Autodesk Fusion 360 part; units mm, degrees
(part 3 of 4)
equation "fix_xbl = door_xbr + ( door_zb - fix_zb ) * ( door_xbr - door_xtr ) / ( door_zt - door_zb ) + glass_gap * sqrt(( door_xbr - door_xtr ) * ( door_xbr - door_xtr ) + ( door_zt - door_zb ) * ( door_zt - door_zb )) / ( door_zt - door_zb )" comment "SKELETON P04 CALCULATION: F-014: fixed glass bottom-left, on the line glass_gap from the door's slanted edge (was v1's 1468)"
equation "fix_xtl = door_xbr + ( door_zb - fix_zt ) * ( door_xbr - door_xtr ) / ( door_zt - door_zb ) + glass_gap * sqrt(( door_xbr - door_xtr ) * ( door_xbr - door_xtr ) + ( door_zt - door_zb ) * ( door_zt - door_zb )) / ( door_zt - door_zb )" comment "SKELETON P04 CALCULATION: F-014: fixed glass top-left, on the same line (was v1's 1184)"
equation "floor_top = mat_t + floor_t" comment "SKELETON P04 CALCULATION: D-72: the floor top, Z 12 (mat 3 + ply 9); the threshold stands thresh_h above the room floor"
equation "wall_z0 = glide_h + band_h" comment "SKELETON P04 CALCULATION: base band top: glides + band"
equation "panel_z0 = wall_z0 + seam_gap" comment "SKELETON P04 CALCULATION: walls stand one seam_gap above the band top (joints register 2.8, IF-01)"
equation "wall_h = pod_h - wall_z0" comment "SKELETON P04 CALCULATION: 2290 = layout study v2_model wall_h"
equation "side_h = ( wall_h - 2 * seam_gap ) / 2" comment "SKELETON P04 CALCULATION: D-23: 2 sheets per side wall; the gap on the band and the horizontal seam (joints register 2.8)"
equation "side_l = wall_depth - seam_gap" comment "SKELETON P04 CALCULATION: side panel length along Y: the seam_gap at the decor's back plate (joints register 2.8, IF-07)"
equation "back_oh = pod_h - outer_t - seam_gap - panel_z0" comment "SKELETON P04 CALCULATION: PM ruling 2026-10-31 (pass D, F-004): the back outer frames run up to the ceiling frame (pod_h - outer_t), less the seam_gap under it, closing the slot at the back top edge"
equation "back_ph = ( back_oh - seam_gap ) / 2" comment "SKELETON P04 CALCULATION: D-23: 4 sheets on the back, two equal rows with one seam_gap between them (joints register 2.8); the lower back linings match the lower row, as on the side walls"
equation "half_pw = ( pod_w - 2 * outer_t - 3 * seam_gap ) / 2" comment "SKELETON P04 CALCULATION: SKIN width of each back and ceiling panel: two skins and three seam_gap seams between the side frames (F-001, joints register 2.8)"
equation "close_gap = 5.5 mm" comment "SKELETON P04 DECIDED: PM ruling 2026-10-31 (joints register, F-011/F-012): frame gap at the closing seams B1-B2, B3-B4 and C1-C2, which have no hard stop (slotted holes, thicker gasket)"
equation "half_fw = ( pod_w - 2 * outer_t - 2 * seam_gap - close_gap ) / 2" comment "SKELETON P04 CALCULATION: FRAME width of each back and ceiling panel: the skins overhang their frames by half_pw - half_fw at the closing seam (PM ruling 2026-10-31)"
equation "inner_w = pod_w - 2 * stack_t" comment "SKELETON P04 CALCULATION: inside width between the side linings"
equation "bolt_edge_inset = 220 mm" comment "SKELETON P04 DECIDED: PM ruling 2026-10-31: on every bolted edge the end bolts sit this far in from each panel end (the FRAME end, where the bolts go), the rest evenly spaced"
equation "spigot_inset = 100 mm" comment "SKELETON P04 DECIDED: PM ruling 2026-10-31: locating spigots this far in from each panel end (round hole at one end, slot at the other)"
equation "base_bolt_edge = bolt_edge_inset" comment "SKELETON P04 DECIDED: J-BASE-01 wall to band: the edge rule (kept by this name for parts already linked)"
equation "n_base_bolt = 4" comment "SKELETON P04 DECIDED: PM ruling 2026-10-31, J-BASE-01: bolts per panel along the band, evenly spaced"
equation "base_spigot_inset = spigot_inset" comment "SKELETON P04 DECIDED: J-BASE-01: the spigot rule (kept by this name for parts already linked)"
equation "base_side_y0 = pod_d / 2 - wall_depth + seam_gap" comment "SKELETON P04 CALCULATION: J-BASE-01: side bolt lines start at the side panel's front end (first bolt base_bolt_edge further on)"
equation "side_base_pitch = ( side_l - 2 * base_bolt_edge ) / ( n_base_bolt - 1 )" comment "SKELETON P04 CALCULATION: J-BASE-01 bolt pitch along a side panel"
equation "base_back_x0 = pod_w / 2 - outer_t - seam_gap" comment "SKELETON P04 CALCULATION: J-BASE-01: back bolt lines start at each back FRAME's outer end, X -/+ this (first bolt base_bolt_edge further in)"
equation "back_base_pitch = ( half_fw - 2 * base_bolt_edge ) / ( n_base_bolt - 1 )" comment "SKELETON P04 DECIDED: PM ruling 2026-10-31 (Reviewer 5 P2 on #58): J-BASE-01 pitch along a back panel, measured on the FRAME (half_fw), where the bolts go; 'panel end' means the frame end"
equation "ceil_bolt_z = pod_h - outer_t + frame_t / 2" comment "SKELETON P04 DECIDED: PM ruling 2026-10-31, J-CEIL-01 wall to ceiling: the bolt line on the ceiling frame's centre (Z 2374)"
equation "n_ceil_side_bolt = 4" comment "SKELETON P04 DECIDED: PM ruling 2026-10-31, J-CEIL-01: bolts along each side wall top"
equation "n_ceil_back_bolt = 4" comment "SKELETON P04 DECIDED: PM ruling 2026-10-31, J-CEIL-01: bolts along each back panel top, like the base (pitch about 253, every edge 350 or less; joints register: 82 bolts in all)"
equation "ceil_side_y0 = pod_d / 2 - wall_depth" comment "SKELETON P04 DECIDED: PM ruling 2026-10-31 (joints register): J-CEIL-01 side bolt lines start at Y -645, measured along the ceiling (first bolt bolt_edge_inset further on)"
equation "ceil_side_pitch = ( wall_depth - 2 * bolt_edge_inset ) / ( n_ceil_side_bolt - 1 )" comment "SKELETON P04 DECIDED: PM ruling 2026-10-31 (joints register): J-CEIL-01 pitch along a side wall top, over the ceiling's length (was over the side panel's)"
equation "ceil_back_x0 = pod_w / 2 - outer_t - seam_gap" comment "SKELETON P04 DECIDED: PM ruling 2026-10-31 (joints register): J-CEIL-01 back bolt lines start at each back frame's outer end, X -/+ this"
equation "ceil_back_pitch = ( half_fw - 2 * bolt_edge_inset ) / ( n_ceil_back_bolt - 1 )" comment "SKELETON P04 DECIDED: PM ruling 2026-10-31 (joints register): J-CEIL-01 pitch along a back panel top, on the frame (half_fw)"
equation "sk_ref = 5000 mm" comment "ASSUMPTION: sketch reference point offset: every sketch corner is dimensioned from a point at -sk_ref on both plane axes, so no dimension changes side when a corner crosses a pod centre line in an edit"
equation "fg_vis_zb = wall_z0" comment "CALCULATION: visible bottom of the fixed pane = the base band top (DL and DR stop there too, PM ruling 2026-10-31)"
equation "fg_vis_zt = dt_zb" comment "CALCULATION: visible top of the fixed pane = DT's underside"
equation "fg_gap = glass_gap" comment "CALCULATION: = the skeleton's glass_gap: the pane's free edge runs parallel to the door's latch edge, 4 mm off (PM ruling 2026-10-31; the skeleton's fix_xbl and fix_xtl follow the same rule since its update #58)"
equation "gu_prof_w = 15 mm" comment "SOURCE: Bohle BO5201571 aluminium U-profile 15 x 15 x 1.5 (hardware selection C5)"
equation "gu_prof_d = 15 mm" comment "SOURCE: as gu_prof_w"
equation "gu_prof_t = 1.5 mm" comment "SOURCE: as gu_prof_w"
equation "gu_w = gu_prof_w - 2 * gu_prof_t" comment "CALCULATION: inner width of the U-profile = the U-seal's outer width"
equation "gu_base = 2 mm" comment "ASSUMPTION: U-seal base under the glass edge; HOLD for Bohle's BO5201735 section drawing"
equation "gu_in_d = gu_prof_d - gu_prof_t" comment "CALCULATION: inner depth of the U-profile"
equation "fg_bite = gu_in_d - gu_base" comment "CALCULATION: glass cover in the hidden channels, 11.5 (PM ruling 2026-10-31); HOLD for the glass supplier's minimum"
equation "fg_r_len = sqrt(( fix_xbr - fix_xk ) * ( fix_xbr - fix_xk ) + ( fix_zk - fix_zb ) * ( fix_zk - fix_zb ))" comment "CALCULATION: length of the skeleton's right edge (bottom-right corner to the knee)"
equation "fg_rnx = ( fix_zk - fix_zb ) / fg_r_len" comment "CALCULATION: right edge outward normal, X"
equation "fg_rnz = ( fix_xk - fix_xbr ) / fg_r_len" comment "CALCULATION: right edge outward normal, Z"
equation "fg_rc = fg_rnx * ( pod_w / 2 - fix_xbr ) + fg_rnz * fix_zb" comment "CALCULATION: right edge line constant"
equation "fg_d_len = sqrt(( pod_w - fix_xtr - fix_xk ) * ( pod_w - fix_xtr - fix_xk ) + ( dt_zb - fix_zk ) * ( dt_zb - fix_zk ))" comment "CALCULATION: length of DR's diagonal inner edge (knee to DT's underside at X -pod_w/2 + fix_xtr)"
equation "fg_dnx = ( dt_zb - fix_zk ) / fg_d_len" comment "CALCULATION: diagonal outward normal, X"
equation "fg_dnz = ( pod_w - fix_xtr - fix_xk ) / fg_d_len" comment "CALCULATION: diagonal outward normal, Z"
equation "fg_dc = fg_dnx * ( pod_w / 2 - fix_xk ) + fg_dnz * fix_zk" comment "CALCULATION: diagonal line constant"
equation "fg_det = fg_rnx * fg_dnz - fg_rnz * fg_dnx" comment "CALCULATION: for the knee corner"
equation "fg_l_len = sqrt(( door_xbr - door_xtr ) * ( door_xbr - door_xtr ) + ( door_zt - door_zb ) * ( door_zt - door_zb ))" comment "CALCULATION: length of the door's latch edge"
equation "fg_lnx = ( door_zt - door_zb ) / fg_l_len" comment "CALCULATION: door latch edge normal toward the pane, X"
equation "fg_lnz = ( door_xbr - door_xtr ) / fg_l_len" comment "CALCULATION: door latch edge normal toward the pane, Z"
equation "fg_lc = fg_lnx * ( -pod_w / 2 + door_xbr ) + fg_lnz * door_zb" comment "CALCULATION: door latch edge line constant"
equation "jf_x = pod_w / 2 - skin_t - bond_t - frame_t / 2" comment "CALCULATION: joints register J-FRONT-01: the side panel's front member centre line, X -/+1224 (skin, bond line and half the 40 frame in from the outside, skeleton named values)"
equation "jf_hole = 9.53 mm" comment "SOURCE: rivnut 838003 (Sherex CAH2-610-4.2, zinc-plated steel, D-131) hole 9.53 +0.10/0, as the aluminium part's (joints register H-03; unverified for the steel part, HOLD-04)"
equation "jf_z1 = panel_z0 + bolt_edge_inset" comment "CALCULATION: lower panel, bottom bolt (220 rule)"
equation "jf_z2 = panel_z0 + side_h / 2" comment "CALCULATION: lower panel, middle bolt"
equation "jf_z3 = panel_z0 + side_h - bolt_edge_inset" comment "CALCULATION: lower panel, top bolt"
equation "jf_z4 = panel_z0 + side_h + seam_gap + bolt_edge_inset" comment "CALCULATION: upper panel, bottom bolt"
equation "jf_z5 = panel_z0 + side_h + seam_gap + side_h / 2" comment "CALCULATION: upper panel, middle bolt"
equation "jf_z6 = panel_z0 + 2 * side_h + seam_gap - bolt_edge_inset" comment "CALCULATION: upper panel, top bolt"
equation "dr_skin_t = 3 mm" comment "SOURCE: ACP 3 mm, EV3038 Dark Yellow (D-12; hardware selection A1)"
equation "dr_fo = dr_skin_t + bond_t" comment "CALCULATION: a frame tube's face from the skin's outer face: the 3 mm ACP and the 3 mm bond line (skeleton bond_t; the bond spec's joint, at least 12 wide x 3 thick, D-137), so every tube that bonds to the skin stands 3 mm off it (PM ruling 2026-11-01)"
equation "dr_back_t = 1.5 mm" comment "CONFIRMED: joints register J-FRONT-01: the back plate is aluminium 1.0 to 2.7 thick at each bolt, for the rivnuts (HOLD-10); 1.5, not 2, so DR stays under 20 kg (D-03; PM ruling 2026-11-01)"
equation "fr_hole_rn = 10 mm" comment "SOURCE: D-163 (PM ruling 2026-11-01): the rivnut 838003 is Sherex CAL2-610-4.2, the knurled round body, in a round drilled hole 10.00 +0.10 (was 9.53 for the half-hex CAH2, whose body needs a hex hole); every rivnut hole in DR, the J-FRONT-01 strip's and the hook studs' too (DL and DT take it in their next rebuild)"
equation "dr_strip_x0 = jf_x - 2 * fr_hole_rn - 0.5 mm" comment "CALCULATION: the fixed back strip's inner edge, 2 hole diameters plus 0.5 from the J-FRONT-01 rivnut holes (mechanical check C09); the rest of the back comes off for the air unit (D-87)"
equation "dr_acc_t = 3 mm" comment "CALCULATION: access panel 3 mm aluminium: it carries the air column's 10 kg on two hook studs 222 mm from its screwed edge (PM ruling 2026-11-01); 2 mm would see about 110 MPa if the column pulls 50 N, 3 mm about 50 MPa"
equation "dr_rn_head = 0.76 mm" comment "SOURCE: rivnut 838003 head 0.76 +/-0.08 (joints register H-03: Sherex CAH2-610-4.2, zinc-plated steel, D-131)"
equation "dr_stop_w = 1.6 mm" comment "SOURCE: an 838004 washer (ISO 7093 6.4 x 18, 1.6 thick) on each rivnut head: the panel's stop (Joints, D-130)"
equation "dr_pnl_gap = dr_rn_head + dr_stop_w" comment "CALCULATION: the inner face panel stands 2.36 off the frame on its stops; the 4.0 seal 848013 is squeezed to it (D-130)"
equation "dr_seal_w = 8 mm" comment "SOURCE: 848013 access panel seal, about 8 wide (joints register H-34; D-130)"
equation "dr_seal_t = 4 mm" comment "SOURCE: 848013 access panel seal, 4.0 thick very soft foam (joints register H-34)"
equation "dr_pitch = 400 mm" comment "SOURCE: the panel's screws about 400 apart (Joints' seal and stop pair, D-130)"
equation "dr_drop = 40 mm" comment "CALCULATION: service: with the column off, the panel drops 40 to clear the soffit's underside (its top edge is 35 over it), then comes out (PM ruling 2026-11-01)"
equation "dr_pull = 100 mm" comment "CALCULATION: service: how far out the model shows the dropped panel coming"
equation "dr_acc_face_y = -pod_d / 2 + decor_d - dr_back_t + dr_pnl_gap + dr_acc_t" comment "CALCULATION: named value for AIR (PM rulings 2026-11-01, D-130): the room-side face of DR's inner face panel, where AIR's air column and soffit start; Y -641.14, the 3 mm panel 2.36 off the frame on its stops"
equation "dr_piece_x0 = 1150 mm" comment "CONFIRMED: with the band behind the soffit dropped, the back plate keeps a short piece from here to the side above the access panel: the soffit stops at X 1161 (AIR), 11 short of it (PM ruling 2026-11-01)"
equation "dr_band_dz = 35 mm" comment "CALCULATION: the back plate's top band starts this far above DT's underside: the removable panels' top edges land 35 on the frame's band tube, so the access panel's top bolts sit 2 hole diameters from its edge and the rivnuts 2 from the tube's edge (C09); the access panel keeps 45 over the opening into the column"
equation "dr_stud_x = 971 mm" comment "SOURCE: PM ruling 2026-11-01 (CEILING): the air column's two hook studs at X 971"
equation "dr_stud_z1 = 1700 mm" comment "SOURCE: PM ruling 2026-11-01 (CEILING): lower hook stud Z 1700"
equation "dr_stud_z2 = 1850 mm" comment "SOURCE: PM ruling 2026-11-01 (CEILING): upper hook stud Z 1850"
equation "felt_t = 9 mm" comment "SOURCE: the factory's 9 mm PET felt (D-31; hardware selection A3)"
equation "dr_col_x0 = 949 mm" comment "SOURCE: air report 7f (AIR #91): the air column's left face, X 949 (column X 949 to 1161)"
equation "dr_col_x1 = 1161 mm" comment "SOURCE: air report 7f (AIR #91; calc.py D60 col): the air column's right edge, X 1161, AIR's named value (D-130)"
equation "dr_f_len = sqrt(dr_xc * dr_xc + ( pod_d / 2 - dr_yc ) * ( pod_d / 2 - dr_yc ))" comment "CALCULATION: length of DR's corner facet in plan"
equation "dr_fnx = ( pod_d / 2 - dr_yc ) / dr_f_len" comment "CALCULATION: corner facet outward normal, X"
equation "dr_fny = -dr_xc / dr_f_len" comment "CALCULATION: corner facet outward normal, Y"
equation "dr_fc = dr_fnx * ( pod_w / 2 - dr_xc ) + dr_fny * ( -pod_d / 2 )" comment "CALCULATION: corner facet line constant"
equation "ri_x0 = 959 mm" comment "SOURCE: the D-60 air table's riser X 956 to 1095, moved 3 mm right with DR's 3 mm bond line so it keeps its 5.9 to B07 (AIR's change, CEILING Engineer 2026-11-01)"
equation "ri_w = 139 mm" comment "SOURCE: D-60 air table: riser 139 wide"
equation "ri_y0 = -803 mm" comment "SOURCE: D-60 air table: riser Y -803 to -648"
equation "ri_d = 155 mm" comment "SOURCE: D-60 air table: riser 155 deep"
equation "ri_zt = 1445 mm" comment "SOURCE: D-60 air table: riser up to Z 1445"
equation "ri_gap = 140 mm" comment "ASSUMPTION: the riser's open foot stands 140 mm over DR's open base, so the air rises straight into it and the riser clears the back frame's inner-edge member B07 by 5.9 mm (the glass line runs to X 950 there; the riser moved 3 mm right with the 3 mm bond line); was 60 before the frame"
equation "slot_clear = 1 mm" comment "ASSUMPTION: fitting clearance each side of the glass channel in DR's skin slot"
equation "ri_t = 1 mm" comment "SOURCE: D-60 air table: 1 mm galvanised steel"
equation "fb_w = 300 mm" comment "SOURCE: D-60 air table: fan box 300 x 155 x 300"
equation "fb_d = 155 mm" comment "SOURCE: D-60 air table"
equation "fb_z0 = 1650 mm" comment "SOURCE: D-60 air table: fan box Z 1650 to 1950"
equation "fb_x0 = 680 mm" comment "SOURCE: fan box left side, X 680 to 980 (PM ruling 2026-11-01, from the AIR Transitions Engineer's check: with the 3 mm bond line the box's lower-left back corner came within 1.0 of the back ring's diagonal B06; 7 mm right it keeps 6.3 to B06, 8.1 to the front ring's diagonal F05 and 17.3 to the fixed glass channel); AIR's model has the same X (sb_x0)"
equation "fb_h = 300 mm" comment "SOURCE: D-60 air table"
equation "fb_t = 2 mm" comment "SOURCE: D-60 air table: 2 mm aluminium"
equation "op_x0 = 961 mm" comment "SOURCE: air report 7f: the opening into the column from X 961"
equation "op_w = 185 mm" comment "SOURCE: the opening X 961 to 1146 (PM ruling 2026-11-01, from the AIR Transitions Engineer: the upper duct's gasket face and every metal edge keep 6 from the bolt-line tube and the band; it ran to the column's edge, 200 x 215)"
equation "op_z0 = 1895 mm" comment "SOURCE: D-60 air table: opening Z 1895 to 2102 (PM ruling 2026-11-01)"
equation "op_h = 207 mm" comment "SOURCE: Z 1895 to 2102 (PM ruling 2026-11-01, the AIR Transitions Engineer; was 215)"
equation "fr_w = 20 mm" comment "CALCULATION: frame tube 20 x 20 x 1.5, 6063-T6 (D-79): bending stiffness E*I = 4.5e8 N.mm2, about v1's 16 x 16 x 1 steel box (4.7e8), at 0.30 kg/m against 0.47"
equation "fr_t = 1.5 mm" comment "CALCULATION: frame tube wall 1.5 where AIR's supply fan box (8.8 kg) stands: the shelf tubes F08 and C03"
equation "fr_t_rn = 1.2 mm" comment "CONFIRMED: wall of the ledge tube B05, which carries DT's two spigot rivnuts: 1.2, as D-85 kept the wall panels' perimeter members for their rivnuts (PM ruling 2026-11-01); the tubes under the inner face panel take fr_t_pnl"
equation "fr_t_pnl = 1.5 mm" comment "SOURCE: wall of the tubes under the inner face panel that take its rivnuts: 1.5 or more, as 1.0 is marginal for an M6 rivnut (Joints, D-130)"
equation "fr_t_sk = 1.0 mm" comment "CONFIRMED: wall of the tubes that only hold the skin and the plates: 1.0, as D-85's inner studs (PM ruling 2026-11-01, DR under 20 kg, D-03); E*I 3.2e8 N.mm2, two thirds of v1's 16 x 16 x 1 steel box, with the ACP bonded on"
equation "fr_wb = 80 mm" comment "CALCULATION: bolt-line tube 80 x 20 x 1.5 behind the fixed strip: the J-FRONT-01 rivnut tails and bolt tips go into it through 14 mm holes (HOLD-10: the plate with the frame behind), and the access panel lands 37 on its other side, wide enough for its bolts and rivnuts at 2 diameters from every edge (C09); 3 clear of the duct spaces"
equation "fr_wbot = 40 mm" comment "ASSUMPTION: back ring's bottom tube 40 x 20 x 1.5: the access panel's lower bolts"
equation "fr_wband = 60 mm" comment "ASSUMPTION: band tube 60 x 20 x 1.5 at DT's underside: the access panel's top bolts and the top band's rivets land on it"
equation "fr_h1 = 724 mm" comment "SOURCE: v1 decor frame drawing (front frame): first cross tube 724 above the bottom"
equation "fb_gap = 5 mm" comment "ASSUMPTION: the fan box's front, clear behind the front ring's cross tube F09"
equation "fb_y0 = -pod_d / 2 + dr_fo + fr_w + fb_gap" comment "CALCULATION: fan box front, Y -819: the D-60 table's -847 moved back behind the cross tube F09 (PM ruling 2026-11-01, D-131), and 3 more with the bond line so F09 keeps its 5 mm (PM ruling 2026-11-01); AIR's model follows (sb_yf)"
equation "fr_hole_jf = 14 mm" comment "CALCULATION: hole in the bolt-line tube's back wall round each J-FRONT-01 rivnut: body 9.50 max and its bulge (SHX), and the bolt tip, go into the tube"
equation "dr_sp_x1 = 1050 mm" comment "CONFIRMED: J-FRONT-02: DR's round spigot hole (PM ruling 2026-11-01)"
equation "dr_sp_x2 = 1147 mm" comment "CONFIRMED: J-FRONT-02: DR's spigot slot, along X (PM ruling 2026-11-01)"
equation "sp_hole = 8.5 mm" comment "SOURCE: R-J13: spigot hole 8.5 round at one end, 8.5 x 14 slot at the other"
equation "sp_slot = 14 mm" comment "SOURCE: R-J13: the slot 14 long along the edge"
equation "dt_sp_x1 = -pod_w / 2 + dt_xr - 179 mm" comment "CONFIRMED: J-FRONT-03: DT's round-hole spigot on DR's ledge, X 270, 36 in from the ledge tube's left end"
equation "dt_sp_dx = 140 mm" comment "CONFIRMED: J-FRONT-03: DT's slot spigot 140 from the first (PM ruling 2026-11-01)"
equation "dt_sp_y = -pod_d / 2 + decor_d - 12.88 mm" comment "CALCULATION: J-FRONT-03: the spigots' Y, -657.88, the middle of where DR's ledge tube and DT's bottom back tube overlap"
equation "ab_hole = 7 mm" comment "SOURCE: the pod's M6 clearance hole, 7.0 (D-64, D-75; the mechanical check's hole rule M6-CLEARANCE-7) for the inner face panel's screws 838001"
equation "ab_x = pod_w / 2 - dr_fo - fr_wb + 2 * fr_hole_rn + 2 mm" comment "CALCULATION: the panel's screw line on the bolt-line tube: the rivnut 2 diameters plus 2 from the tube's inner edge (C09)"
equation "ab_zt = fg_vis_zt + 2 * fr_hole_rn + 1 mm" comment "CALCULATION: the panel's screw line on the band tube: its rivnuts 2 diameters plus 1 above the tube's lower edge (C09)"
equation "dr_sc_clear = 40 mm" comment "CALCULATION: the panel's end screws 40 from the corners of its screw line, clear of the frame's welded corners (D-130)"
equation "dr_hd_d = 12 mm" comment "SOURCE: a plain M6 washer 838011 under each panel screw's head, ISO 7089 6.4 x 12 x 1.6, 200 HV zinc-plated steel (PM rulings 2026-11-01: the socket heads stay, one 5 mm key on site; the 18 mm washer made every felt hole break out; joints register H-44)"
equation "dr_felt_web = 3 mm" comment "CALCULATION: felt left between each felt hole and the felt's edge (PM ruling 2026-11-01)"
equation "dr_felt_hole = dr_hd_d + 2 mm" comment "CALCULATION: closed felt holes over the panel's screw heads: the washer and 1 mm round it, each plugged with felt cut from the same sheet (no bare socket heads on the room side); the screws stand 10 from the felt's edges, so dr_felt_web stays (PM rulings 2026-11-01)"
equation "dr_cl = sqrt(( pod_d / 2 - ch_yb ) * ( pod_d / 2 - ch_yb ) + ( pod_h - ch_zlo ) * ( pod_h - ch_zlo ))" comment "CALCULATION: length of the top chamfer in the side view"
equation "dr_cny = -( pod_h - ch_zlo ) / dr_cl" comment "CALCULATION: top chamfer outward normal, Y"
equation "dr_cnz = ( pod_d / 2 - ch_yb ) / dr_cl" comment "CALCULATION: top chamfer outward normal, Z"
equation "dr_cc = dr_cny * ( -pod_d / 2 ) + dr_cnz * ch_zlo" comment "CALCULATION: top chamfer line constant"
equation "dr_jl = sqrt(( dt_xr - fix_xtr ) * ( dt_xr - fix_xtr ) + ( pod_d / 2 - ch_yb ) * ( pod_d / 2 - ch_yb ))" comment "CALCULATION: length of the DR-DT joint line in plan (v1's line to X 449)"
equation "dr_jnx = ( pod_d / 2 - ch_yb ) / dr_jl" comment "CALCULATION: DR-DT joint normal into DR, X"
equation "dr_jny = -( dt_xr - fix_xtr ) / dr_jl" comment "CALCULATION: DR-DT joint normal into DR, Y"
equation "dr_jc = dr_jnx * ( -pod_w / 2 + fix_xtr ) + dr_jny * ( -pod_d / 2 )" comment "CALCULATION: DR-DT joint line constant"
equation "dr_pl0x = ( ( fg_rc + dr_fo + fr_w / 2 - ( ( fg_vis_zb + fr_wbot / 2 ) * fg_rnz ) ) / fg_rnx )" comment "CALCULATION: the inner face panel's screw line, corner 0, X"
equation "dr_pl0z = ( ( fg_rnx * ( fg_vis_zb + fr_wbot / 2 ) ) / fg_rnx )" comment "CALCULATION: the inner face panel's screw line, corner 0, Z"
equation "dr_pl1x = ( -( -ab_x ) )" comment "CALCULATION: the inner face panel's screw line, corner 1, X"
equation "dr_pl1z = ( -( -( fg_vis_zb + fr_wbot / 2 ) ) )" comment "CALCULATION: the inner face panel's screw line, corner 1, Z"
equation "dr_pl2x = ( -( -ab_x ) )" comment "CALCULATION: the inner face panel's screw line, corner 2, X"
equation "dr_pl2z = ( -( -ab_zt ) )" comment "CALCULATION: the inner face panel's screw line, corner 2, Z"
equation "dr_pl3x = ( -( -( -pod_w / 2 + dt_xr + fr_w / 2 ) ) )" comment "CALCULATION: the inner face panel's screw line, corner 3, X"
equation "dr_pl3z = ( -( -ab_zt ) )" comment "CALCULATION: the inner face panel's screw line, corner 3, Z"
equation "dr_pl4x = ( -( -( -pod_w / 2 + dt_xr + fr_w / 2 ) ) )" comment "CALCULATION: the inner face panel's screw line, corner 4, X"
equation "dr_pl4z = ( -( -( fg_vis_zt - fr_w / 2 ) ) )" comment "CALCULATION: the inner face panel's screw line, corner 4, Z"
equation "dr_pl5x = ( ( ( -( fg_vis_zt - fr_w / 2 ) ) * fg_dnz - ( -( fg_dc + dr_fo + fr_w / 2 ) ) ) / ( -( -fg_dnx ) ) )" comment "CALCULATION: the inner face panel's screw line, corner 5, X"
equation "dr_pl5z = ( ( -( fg_dnx * ( -( fg_vis_zt - fr_w / 2 ) ) ) ) / ( -( -fg_dnx ) ) )" comment "CALCULATION: the inner face panel's screw line, corner 5, Z"
equation "dr_pl6x = ( ( ( fg_dc + dr_fo + fr_w / 2 ) * fg_rnz - ( ( fg_rc + dr_fo + fr_w / 2 ) * fg_dnz ) ) / ( fg_dnx * fg_rnz - ( fg_rnx * fg_dnz ) ) )" comment "CALCULATION: the inner face panel's screw line, corner 6, X"
equation "dr_pl6z = ( ( fg_dnx * ( fg_rc + dr_fo + fr_w / 2 ) - ( fg_rnx * ( fg_dc + dr_fo + fr_w / 2 ) ) ) / ( fg_dnx * fg_rnz - ( fg_rnx * fg_dnz ) ) )" comment "CALCULATION: the inner face panel's screw line, corner 6, Z"
equation "dr_pe0 = sqrt(( dr_pl1x - dr_pl0x ) * ( dr_pl1x - dr_pl0x ) + ( dr_pl1z - dr_pl0z ) * ( dr_pl1z - dr_pl0z ))" comment "CALCULATION: the inner face panel's screw line along tube B01, its length"
equation "dr_pe1 = sqrt(( dr_pl2x - dr_pl1x ) * ( dr_pl2x - dr_pl1x ) + ( dr_pl2z - dr_pl1z ) * ( dr_pl2z - dr_pl1z ))" comment "CALCULATION: the inner face panel's screw line along tube B02, its length"
equation "dr_pe2 = sqrt(( dr_pl3x - dr_pl2x ) * ( dr_pl3x - dr_pl2x ) + ( dr_pl3z - dr_pl2z ) * ( dr_pl3z - dr_pl2z ))" comment "CALCULATION: the inner face panel's screw line along tube B08, its length"
equation "dr_pe3 = sqrt(( dr_pl4x - dr_pl3x ) * ( dr_pl4x - dr_pl3x ) + ( dr_pl4z - dr_pl3z ) * ( dr_pl4z - dr_pl3z ))" comment "CALCULATION: the inner face panel's screw line along tube B04, its length"
equation "dr_pe4 = sqrt(( dr_pl5x - dr_pl4x ) * ( dr_pl5x - dr_pl4x ) + ( dr_pl5z - dr_pl4z ) * ( dr_pl5z - dr_pl4z ))" comment "CALCULATION: the inner face panel's screw line along tube B05, its length"
equation "dr_pe5 = sqrt(( dr_pl6x - dr_pl5x ) * ( dr_pl6x - dr_pl5x ) + ( dr_pl6z - dr_pl5z ) * ( dr_pl6z - dr_pl5z ))" comment "CALCULATION: the inner face panel's screw line along tube B06, its length"
equation "dr_pe6 = sqrt(( dr_pl0x - dr_pl6x ) * ( dr_pl0x - dr_pl6x ) + ( dr_pl0z - dr_pl6z ) * ( dr_pl0z - dr_pl6z ))" comment "CALCULATION: the inner face panel's screw line along tube B07, its length"
equation "dr_sc_b08 = ab_x - ( pod_w / 2 - dr_fo - fr_wb ) + 2 * fr_hole_rn + 0.5 mm" comment "CALCULATION: the band tube B08's screw by the bolt-line tube from the screw line's corner: two rivnut-hole diameters and 0.5 from B08's square end at the bolt-line tube (C09's rule)"
equation "dr_sc_col = ( dr_pl0x - ( dr_col_x0 - dr_felt_hole / 2 - dr_felt_web ) ) * dr_pe6 / ( dr_pl0x - dr_pl6x )" comment "CALCULATION: the glass-edge tube B07's lowest screw from the screw line's bottom corner: its felt hole keeps dr_felt_web of felt at the air column's edge (X dr_col_x0) and its washer stands clear of the column's left face (PM ruling 2026-11-01)"
equation "d8636 = sk_ref"
equation "d8637 = sk_ref"
equation "d8638 = ( ( ( fg_rc + 0 mm - fg_rnz * ( ( fg_vis_zb - 0 mm ) ) ) / fg_rnx ) ) + sk_ref"
equation "d8639 = ( pod_w / 2 ) + sk_ref"
equation "d8640 = ( -pod_w / 2 + fix_xtr ) + sk_ref"
equation "d8641 = ( ( ( ( fg_rc + 0 mm ) * fg_dnz - ( fg_dc + 0 mm ) * fg_rnz ) / fg_det ) ) + sk_ref"
equation "d8642 = ( ( fg_vis_zb - 0 mm ) ) + sk_ref"
equation "d8643 = ( pod_h ) + sk_ref"
equation "d8644 = ( ( fg_vis_zt + 0 mm ) ) + sk_ref"
equation "d8645 = ( ( ( fg_rnx * ( fg_dc + 0 mm ) - fg_dnx * ( fg_rc + 0 mm ) ) / fg_det ) ) + sk_ref"
equation "d8646 = ( -pod_d / 2 ) * ( 1 )"
equation "d8647 = ( -pod_d / 2 + decor_d ) - ( -pod_d / 2 )"
equation "d8649 = sk_ref"
equation "d8650 = sk_ref"
equation "d8651 = ( pod_w / 2 - dr_xc ) + sk_ref"
equation "d8652 = ( pod_w / 2 ) + sk_ref"
equation "d8653 = ( -dr_yc ) + sk_ref"
equation "d8654 = ( -pod_d / 2 ) + sk_ref"
equation "d8655 = ( 0 mm ) * ( 1 )"
equation "d8656 = ( pod_h ) - ( 0 mm )"
equation "d8658 = sk_ref"
equation "d8659 = sk_ref"
equation "d8660 = ( -pod_w / 2 + dt_xr ) + sk_ref"
equation "d8661 = ( -pod_w / 2 + fix_xtr ) + sk_ref"
equation "d8662 = ( -pod_d / 2 ) + sk_ref"
equation "d8663 = ( -ch_yb ) + sk_ref"
equation "d8664 = ( -pod_d / 2 + decor_d ) + sk_ref"
equation "d8665 = ( dt_zb ) * ( 1 )"
equation "d8666 = ( pod_h ) - ( dt_zb )"
equation "d8668 = sk_ref"
equation "d8669 = sk_ref"
equation "d8670 = ( ch_zlo ) + sk_ref"
equation "d8671 = ( pod_h ) + sk_ref"
equation "d8672 = ( -ch_yb ) + sk_ref"
equation "d8673 = ( -pod_d / 2 ) + sk_ref"
equation "d8674 = ( -pod_w / 2 ) * ( 1 )"
equation "d8675 = ( pod_w / 2 ) - ( -pod_w / 2 )"
equation "d8677 = dr_skin_t"
equation "d8678 = sk_ref"
equation "d8679 = sk_ref"
equation "d8680 = ( ( ( fg_rc + 0 mm - fg_rnz * ( fg_vis_zb ) ) / fg_rnx ) ) + sk_ref"
equation "d8681 = ( ( ( fg_rc + gu_prof_d - fg_rnz * ( fg_vis_zb ) ) / fg_rnx ) ) + sk_ref"
equation "d8682 = ( ( ( ( fg_rc + gu_prof_d ) * fg_dnz - ( fg_dc + gu_prof_d ) * fg_rnz ) / fg_det ) ) + sk_ref"
equation "d8683 = ( ( ( fg_dc + gu_prof_d - fg_dnz * ( fg_vis_zt ) ) / fg_dnx ) ) + sk_ref"
equation "d8684 = ( ( ( fg_dc + 0 mm - fg_dnz * ( fg_vis_zt ) ) / fg_dnx ) ) + sk_ref"
equation "d8685 = ( ( ( ( fg_rc + 0 mm ) * fg_dnz - ( fg_dc + 0 mm ) * fg_rnz ) / fg_det ) ) + sk_ref"
equation "d8686 = ( fg_vis_zb ) + sk_ref"
equation "d8687 = ( ( ( fg_rnx * ( fg_dc + gu_prof_d ) - fg_dnx * ( fg_rc + gu_prof_d ) ) / fg_det ) ) + sk_ref"
equation "d8688 = ( fg_vis_zt ) + sk_ref"
equation "d8689 = ( ( ( fg_rnx * ( fg_dc + 0 mm ) - fg_dnx * ( fg_rc + 0 mm ) ) / fg_det ) ) + sk_ref"
equation "d8690 = ( -glass_y - gu_prof_w / 2 - slot_clear ) * ( 1 )"
equation "d8691 = ( -glass_y + gu_prof_w / 2 + slot_clear ) - ( -glass_y - gu_prof_w / 2 - slot_clear )"
equation "d8693 = sk_ref"
equation "d8694 = sk_ref"
equation "d8695 = ( ( ( dr_fc - dr_skin_t - dr_fny * ( -pod_d / 2 + dr_skin_t ) ) / dr_fnx ) ) + sk_ref"
equation "d8696 = ( ( pod_w / 2 - dr_skin_t ) ) + sk_ref"
equation "d8697 = ( ( ( fg_rc + dr_skin_t - fg_rnz * ( fg_vis_zb + dr_skin_t ) ) / fg_rnx ) ) + sk_ref"
equation "d8698 = ( ( -pod_d / 2 + dr_skin_t ) ) + sk_ref"
equation "d8699 = ( ( ( dr_fc - dr_skin_t - dr_fnx * ( pod_w / 2 - dr_skin_t ) ) / dr_fny ) ) + sk_ref"
equation "d8700 = ( -pod_d / 2 + decor_d - dr_back_t ) + sk_ref"
equation "d8701 = ( fg_vis_zb - 1 mm ) * ( 1 )"
equation "d8702 = ( fg_vis_zb + dr_skin_t + 1 mm ) - ( fg_vis_zb - 1 mm )"
equation "d8704 = sk_ref"
equation "d8705 = sk_ref"
equation "d8706 = ( pod_w / 2 - dr_skin_t ) + sk_ref"
equation "d8707 = ( -pod_w / 2 + dt_xr ) + sk_ref"
equation "d8708 = ( dr_strip_x0 ) + sk_ref"
equation "d8709 = ( fg_vis_zb + dr_skin_t ) + sk_ref"
equation "d8710 = ( pod_h - dr_skin_t ) + sk_ref"
equation "d8711 = ( fg_vis_zt + dr_band_dz ) + sk_ref"
equation "d8712 = ( -pod_d / 2 + decor_d - dr_back_t ) * ( 1 )"
equation "d8713 = ( -pod_d / 2 + decor_d ) - ( -pod_d / 2 + decor_d - dr_back_t )"
equation "d8715 = sk_ref"
equation "d8716 = sk_ref"
equation "d8717 = ( jf_x ) + sk_ref"
equation "d8718 = ( jf_z1 ) + sk_ref"
equation "d8719 = fr_hole_rn"
equation "d8720 = ( jf_x ) + sk_ref"
equation "d8721 = ( jf_z2 ) + sk_ref"
equation "d8722 = fr_hole_rn"
equation "d8723 = ( jf_x ) + sk_ref"
equation "d8724 = ( jf_z3 ) + sk_ref"
equation "d8725 = fr_hole_rn"
equation "d8726 = ( jf_x ) + sk_ref"
equation "d8727 = ( jf_z4 ) + sk_ref"
equation "d8728 = fr_hole_rn"
equation "d8729 = ( jf_x ) + sk_ref"
equation "d8730 = ( jf_z5 ) + sk_ref"
equation "d8731 = fr_hole_rn"
equation "d8732 = ( jf_x ) + sk_ref"
equation "d8733 = ( jf_z6 ) + sk_ref"
equation "d8734 = fr_hole_rn"
equation "d8735 = ( -pod_d / 2 + decor_d - dr_back_t - 1 mm ) * ( 1 )"
equation "d8736 = ( -pod_d / 2 + decor_d + 1 mm ) - ( -pod_d / 2 + decor_d - dr_back_t - 1 mm )"
equation "d8738 = sk_ref"
equation "d8739 = sk_ref"
equation "d8740 = ( ( ( fg_rc + dr_skin_t - fg_rnz * ( fg_vis_zb + dr_skin_t ) ) / fg_rnx ) ) + sk_ref"
equation "d8741 = ( dr_strip_x0 ) + sk_ref"
equation "d8742 = ( -pod_w / 2 + dt_xr ) + sk_ref"
equation "d8743 = ( ( ( fg_dc + dr_skin_t - fg_dnz * ( fg_vis_zt ) ) / fg_dnx ) ) + sk_ref"
equation "d8744 = ( ( ( ( fg_rc + dr_skin_t ) * fg_dnz - ( fg_dc + dr_skin_t ) * fg_rnz ) / fg_det ) ) + sk_ref"
equation "d8745 = ( fg_vis_zb + dr_skin_t ) + sk_ref"
equation "d8746 = ( fg_vis_zt + dr_band_dz ) + sk_ref"
equation "d8747 = ( fg_vis_zt ) + sk_ref"
equation "d8748 = ( ( ( fg_rnx * ( fg_dc + dr_skin_t ) - fg_dnx * ( fg_rc + dr_skin_t ) ) / fg_det ) ) + sk_ref"
equation "d8749 = ( dr_acc_face_y - dr_acc_t ) * ( 1 )"
equation "d8750 = ( dr_acc_face_y ) - ( dr_acc_face_y - dr_acc_t )"
equation "d8752 = sk_ref"
equation "d8753 = sk_ref"
equation "d8754 = ( op_x0 + op_w ) + sk_ref"
equation "d8755 = ( op_x0 ) + sk_ref"
equation "d8756 = ( op_z0 ) + sk_ref"
equation "d8757 = ( op_z0 + op_h ) + sk_ref"
equation "d8758 = ( dr_acc_face_y - dr_acc_t - 1 mm ) * ( 1 )"
equation "d8759 = ( dr_acc_face_y + 1 mm ) - ( dr_acc_face_y - dr_acc_t - 1 mm )"
equation "d8761 = sk_ref"
equation "d8762 = sk_ref"
equation "d8763 = ( dr_pl0x + ( dr_pl1x - dr_pl0x ) * ( ( dr_sc_clear + 0 * ( dr_pe0 - dr_sc_clear - dr_sc_clear ) / 1 ) / dr_pe0 ) ) + sk_ref"
equation "d8764 = ( dr_pl0z + ( dr_pl1z - dr_pl0z ) * ( ( dr_sc_clear + 0 * ( dr_pe0 - dr_sc_clear - dr_sc_clear ) / 1 ) / dr_pe0 ) ) + sk_ref"
equation "d8765 = ab_hole"
equation "d8766 = ( dr_pl0x + ( dr_pl1x - dr_pl0x ) * ( ( dr_sc_clear + 1 * ( dr_pe0 - dr_sc_clear - dr_sc_clear ) / 1 ) / dr_pe0 ) ) + sk_ref"
equation "d8767 = ( dr_pl0z + ( dr_pl1z - dr_pl0z ) * ( ( dr_sc_clear + 1 * ( dr_pe0 - dr_sc_clear - dr_sc_clear ) / 1 ) / dr_pe0 ) ) + sk_ref"
equation "d8768 = ab_hole"
equation "d8769 = ( dr_pl1x + ( dr_pl2x - dr_pl1x ) * ( ( dr_sc_clear + 0 * ( dr_pe1 - dr_sc_clear - dr_sc_clear ) / 5 ) / dr_pe1 ) ) + sk_ref"
equation "d8770 = ( dr_pl1z + ( dr_pl2z - dr_pl1z ) * ( ( dr_sc_clear + 0 * ( dr_pe1 - dr_sc_clear - dr_sc_clear ) / 5 ) / dr_pe1 ) ) + sk_ref"
equation "d8771 = ab_hole"
equation "d8772 = ( dr_pl1x + ( dr_pl2x - dr_pl1x ) * ( ( dr_sc_clear + 1 * ( dr_pe1 - dr_sc_clear - dr_sc_clear ) / 5 ) / dr_pe1 ) ) + sk_ref"
equation "d8773 = ( dr_pl1z + ( dr_pl2z - dr_pl1z ) * ( ( dr_sc_clear + 1 * ( dr_pe1 - dr_sc_clear - dr_sc_clear ) / 5 ) / dr_pe1 ) ) + sk_ref"
equation "d8774 = ab_hole"
equation "d8775 = ( dr_pl1x + ( dr_pl2x - dr_pl1x ) * ( ( dr_sc_clear + 2 * ( dr_pe1 - dr_sc_clear - dr_sc_clear ) / 5 ) / dr_pe1 ) ) + sk_ref"
equation "d8776 = ( dr_pl1z + ( dr_pl2z - dr_pl1z ) * ( ( dr_sc_clear + 2 * ( dr_pe1 - dr_sc_clear - dr_sc_clear ) / 5 ) / dr_pe1 ) ) + sk_ref"
equation "d8777 = ab_hole"
equation "d8778 = ( dr_pl1x + ( dr_pl2x - dr_pl1x ) * ( ( dr_sc_clear + 3 * ( dr_pe1 - dr_sc_clear - dr_sc_clear ) / 5 ) / dr_pe1 ) ) + sk_ref"
equation "d8779 = ( dr_pl1z + ( dr_pl2z - dr_pl1z ) * ( ( dr_sc_clear + 3 * ( dr_pe1 - dr_sc_clear - dr_sc_clear ) / 5 ) / dr_pe1 ) ) + sk_ref"
equation "d8780 = ab_hole"
equation "d8781 = ( dr_pl1x + ( dr_pl2x - dr_pl1x ) * ( ( dr_sc_clear + 4 * ( dr_pe1 - dr_sc_clear - dr_sc_clear ) / 5 ) / dr_pe1 ) ) + sk_ref"
equation "d8782 = ( dr_pl1z + ( dr_pl2z - dr_pl1z ) * ( ( dr_sc_clear + 4 * ( dr_pe1 - dr_sc_clear - dr_sc_clear ) / 5 ) / dr_pe1 ) ) + sk_ref"
equation "d8783 = ab_hole"
equation "d8784 = ( dr_pl1x + ( dr_pl2x - dr_pl1x ) * ( ( dr_sc_clear + 5 * ( dr_pe1 - dr_sc_clear - dr_sc_clear ) / 5 ) / dr_pe1 ) ) + sk_ref"
equation "d8785 = ( dr_pl1z + ( dr_pl2z - dr_pl1z ) * ( ( dr_sc_clear + 5 * ( dr_pe1 - dr_sc_clear - dr_sc_clear ) / 5 ) / dr_pe1 ) ) + sk_ref"
equation "d8786 = ab_hole"
equation "d8787 = ( dr_pl2x + ( dr_pl3x - dr_pl2x ) * ( ( dr_sc_b08 + 0 * ( dr_pe2 - dr_sc_b08 - dr_sc_clear ) / 2 ) / dr_pe2 ) ) + sk_ref"
equation "d8788 = ( dr_pl2z + ( dr_pl3z - dr_pl2z ) * ( ( dr_sc_b08 + 0 * ( dr_pe2 - dr_sc_b08 - dr_sc_clear ) / 2 ) / dr_pe2 ) ) + sk_ref"
equation "d8789 = ab_hole"
equation "d8790 = ( dr_pl2x + ( dr_pl3x - dr_pl2x ) * ( ( dr_sc_b08 + 1 * ( dr_pe2 - dr_sc_b08 - dr_sc_clear ) / 2 ) / dr_pe2 ) ) + sk_ref"
equation "d8791 = ( dr_pl2z + ( dr_pl3z - dr_pl2z ) * ( ( dr_sc_b08 + 1 * ( dr_pe2 - dr_sc_b08 - dr_sc_clear ) / 2 ) / dr_pe2 ) ) + sk_ref"
equation "d8792 = ab_hole"
equation "d8793 = ( dr_pl2x + ( dr_pl3x - dr_pl2x ) * ( ( dr_sc_b08 + 2 * ( dr_pe2 - dr_sc_b08 - dr_sc_clear ) / 2 ) / dr_pe2 ) ) + sk_ref"
equation "d8794 = ( dr_pl2z + ( dr_pl3z - dr_pl2z ) * ( ( dr_sc_b08 + 2 * ( dr_pe2 - dr_sc_b08 - dr_sc_clear ) / 2 ) / dr_pe2 ) ) + sk_ref"
equation "d8795 = ab_hole"
equation "d8796 = ( dr_pl4x + ( dr_pl5x - dr_pl4x ) * ( ( dr_sc_clear + 0 * ( dr_pe4 - dr_sc_clear - dr_sc_clear ) / 1 ) / dr_pe4 ) ) + sk_ref"
equation "d8797 = ( dr_pl4z + ( dr_pl5z - dr_pl4z ) * ( ( dr_sc_clear + 0 * ( dr_pe4 - dr_sc_clear - dr_sc_clear ) / 1 ) / dr_pe4 ) ) + sk_ref"
equation "d8798 = ab_hole"
equation "d8799 = ( dr_pl4x + ( dr_pl5x - dr_pl4x ) * ( ( dr_sc_clear + 1 * ( dr_pe4 - dr_sc_clear - dr_sc_clear ) / 1 ) / dr_pe4 ) ) + sk_ref"
equation "d8800 = ( dr_pl4z + ( dr_pl5z - dr_pl4z ) * ( ( dr_sc_clear + 1 * ( dr_pe4 - dr_sc_clear - dr_sc_clear ) / 1 ) / dr_pe4 ) ) + sk_ref"
equation "d8801 = ab_hole"
equation "d8802 = ( dr_pl5x + ( dr_pl6x - dr_pl5x ) * ( ( dr_sc_clear + 0 * ( dr_pe5 - dr_sc_clear - dr_sc_clear ) / 2 ) / dr_pe5 ) ) + sk_ref"
equation "d8803 = ( dr_pl5z + ( dr_pl6z - dr_pl5z ) * ( ( dr_sc_clear + 0 * ( dr_pe5 - dr_sc_clear - dr_sc_clear ) / 2 ) / dr_pe5 ) ) + sk_ref"
equation "d8804 = ab_hole"
equation "d8805 = ( dr_pl5x + ( dr_pl6x - dr_pl5x ) * ( ( dr_sc_clear + 1 * ( dr_pe5 - dr_sc_clear - dr_sc_clear ) / 2 ) / dr_pe5 ) ) + sk_ref"
equation "d8806 = ( dr_pl5z + ( dr_pl6z - dr_pl5z ) * ( ( dr_sc_clear + 1 * ( dr_pe5 - dr_sc_clear - dr_sc_clear ) / 2 ) / dr_pe5 ) ) + sk_ref"
equation "d8807 = ab_hole"
equation "d8808 = ( dr_pl5x + ( dr_pl6x - dr_pl5x ) * ( ( dr_sc_clear + 2 * ( dr_pe5 - dr_sc_clear - dr_sc_clear ) / 2 ) / dr_pe5 ) ) + sk_ref"
equation "d8809 = ( dr_pl5z + ( dr_pl6z - dr_pl5z ) * ( ( dr_sc_clear + 2 * ( dr_pe5 - dr_sc_clear - dr_sc_clear ) / 2 ) / dr_pe5 ) ) + sk_ref"
equation "d8810 = ab_hole"
equation "d8811 = ( dr_pl6x + ( dr_pl0x - dr_pl6x ) * ( ( dr_sc_clear + 0 * ( dr_pe6 - dr_sc_clear - dr_sc_col ) / 4 ) / dr_pe6 ) ) + sk_ref"
equation "d8812 = ( dr_pl6z + ( dr_pl0z - dr_pl6z ) * ( ( dr_sc_clear + 0 * ( dr_pe6 - dr_sc_clear - dr_sc_col ) / 4 ) / dr_pe6 ) ) + sk_ref"
equation "d8813 = ab_hole"
equation "d8814 = ( dr_pl6x + ( dr_pl0x - dr_pl6x ) * ( ( dr_sc_clear + 1 * ( dr_pe6 - dr_sc_clear - dr_sc_col ) / 4 ) / dr_pe6 ) ) + sk_ref"
equation "d8815 = ( dr_pl6z + ( dr_pl0z - dr_pl6z ) * ( ( dr_sc_clear + 1 * ( dr_pe6 - dr_sc_clear - dr_sc_col ) / 4 ) / dr_pe6 ) ) + sk_ref"
equation "d8816 = ab_hole"
equation "d8817 = ( dr_pl6x + ( dr_pl0x - dr_pl6x ) * ( ( dr_sc_clear + 2 * ( dr_pe6 - dr_sc_clear - dr_sc_col ) / 4 ) / dr_pe6 ) ) + sk_ref"
equation "d8818 = ( dr_pl6z + ( dr_pl0z - dr_pl6z ) * ( ( dr_sc_clear + 2 * ( dr_pe6 - dr_sc_clear - dr_sc_col ) / 4 ) / dr_pe6 ) ) + sk_ref"
equation "d8819 = ab_hole"
equation "d8820 = ( dr_pl6x + ( dr_pl0x - dr_pl6x ) * ( ( dr_sc_clear + 3 * ( dr_pe6 - dr_sc_clear - dr_sc_col ) / 4 ) / dr_pe6 ) ) + sk_ref"
equation "d8821 = ( dr_pl6z + ( dr_pl0z - dr_pl6z ) * ( ( dr_sc_clear + 3 * ( dr_pe6 - dr_sc_clear - dr_sc_col ) / 4 ) / dr_pe6 ) ) + sk_ref"
equation "d8822 = ab_hole"
equation "d8823 = ( dr_pl6x + ( dr_pl0x - dr_pl6x ) * ( ( dr_sc_clear + 4 * ( dr_pe6 - dr_sc_clear - dr_sc_col ) / 4 ) / dr_pe6 ) ) + sk_ref"
equation "d8824 = ( dr_pl6z + ( dr_pl0z - dr_pl6z ) * ( ( dr_sc_clear + 4 * ( dr_pe6 - dr_sc_clear - dr_sc_col ) / 4 ) / dr_pe6 ) ) + sk_ref"
equation "d8825 = ab_hole"
equation "d8826 = ( dr_acc_face_y - dr_acc_t - 1 mm ) * ( 1 )"
equation "d8827 = ( dr_acc_face_y + 1 mm ) - ( dr_acc_face_y - dr_acc_t - 1 mm )"
equation "d8829 = sk_ref"
equation "d8830 = sk_ref"
equation "d8831 = ( dr_stud_x ) + sk_ref"
equation "d8832 = ( dr_stud_z1 ) + sk_ref"
equation "d8833 = fr_hole_rn"
equation "d8834 = ( dr_stud_x ) + sk_ref"
equation "d8835 = ( dr_stud_z2 ) + sk_ref"
equation "d8836 = fr_hole_rn"
equation "d8837 = ( dr_acc_face_y - dr_acc_t - 1 mm ) * ( 1 )"
equation "d8838 = ( dr_acc_face_y + 1 mm ) - ( dr_acc_face_y - dr_acc_t - 1 mm )"
equation "d8840 = sk_ref"
equation "d8841 = sk_ref"
equation "d8842 = ( dr_col_x0 ) + sk_ref"
equation "d8843 = ( ( ( fg_dc + dr_skin_t - fg_dnz * ( fg_vis_zt ) ) / fg_dnx ) ) + sk_ref"
equation "d8844 = ( ( ( ( fg_rc + dr_skin_t ) * fg_dnz - ( fg_dc + dr_skin_t ) * fg_rnz ) / fg_det ) ) + sk_ref"
equation "d8845 = ( ( ( fg_rc + dr_skin_t - fg_rnx * dr_col_x0 ) / fg_rnz ) ) + sk_ref"
equation "d8846 = ( fg_vis_zt ) + sk_ref"
equation "d8847 = ( ( ( fg_rnx * ( fg_dc + dr_skin_t ) - fg_dnx * ( fg_rc + dr_skin_t ) ) / fg_det ) ) + sk_ref"
equation "d8848 = ( dr_acc_face_y ) * ( 1 )"
equation "d8849 = ( dr_acc_face_y + felt_t ) - ( dr_acc_face_y )"
equation "d8851 = sk_ref"
equation "d8852 = sk_ref"
equation "d8853 = ( dr_pl4x + ( dr_pl5x - dr_pl4x ) * ( ( dr_sc_clear + 0 * ( dr_pe4 - dr_sc_clear - dr_sc_clear ) / 1 ) / dr_pe4 ) ) + sk_ref"
equation "d8854 = ( dr_pl4z + ( dr_pl5z - dr_pl4z ) * ( ( dr_sc_clear + 0 * ( dr_pe4 - dr_sc_clear - dr_sc_clear ) / 1 ) / dr_pe4 ) ) + sk_ref"
equation "d8855 = dr_felt_hole"
equation "d8856 = ( dr_pl4x + ( dr_pl5x - dr_pl4x ) * ( ( dr_sc_clear + 1 * ( dr_pe4 - dr_sc_clear - dr_sc_clear ) / 1 ) / dr_pe4 ) ) + sk_ref"
equation "d8857 = ( dr_pl4z + ( dr_pl5z - dr_pl4z ) * ( ( dr_sc_clear + 1 * ( dr_pe4 - dr_sc_clear - dr_sc_clear ) / 1 ) / dr_pe4 ) ) + sk_ref"
equation "d8858 = dr_felt_hole"
equation "d8859 = ( dr_pl5x + ( dr_pl6x - dr_pl5x ) * ( ( dr_sc_clear + 0 * ( dr_pe5 - dr_sc_clear - dr_sc_clear ) / 2 ) / dr_pe5 ) ) + sk_ref"
equation "d8860 = ( dr_pl5z + ( dr_pl6z - dr_pl5z ) * ( ( dr_sc_clear + 0 * ( dr_pe5 - dr_sc_clear - dr_sc_clear ) / 2 ) / dr_pe5 ) ) + sk_ref"
equation "d8861 = dr_felt_hole"
equation "d8862 = ( dr_pl5x + ( dr_pl6x - dr_pl5x ) * ( ( dr_sc_clear + 1 * ( dr_pe5 - dr_sc_clear - dr_sc_clear ) / 2 ) / dr_pe5 ) ) + sk_ref"
equation "d8863 = ( dr_pl5z + ( dr_pl6z - dr_pl5z ) * ( ( dr_sc_clear + 1 * ( dr_pe5 - dr_sc_clear - dr_sc_clear ) / 2 ) / dr_pe5 ) ) + sk_ref"
equation "d8864 = dr_felt_hole"
equation "d8865 = ( dr_pl5x + ( dr_pl6x - dr_pl5x ) * ( ( dr_sc_clear + 2 * ( dr_pe5 - dr_sc_clear - dr_sc_clear ) / 2 ) / dr_pe5 ) ) + sk_ref"
equation "d8866 = ( dr_pl5z + ( dr_pl6z - dr_pl5z ) * ( ( dr_sc_clear + 2 * ( dr_pe5 - dr_sc_clear - dr_sc_clear ) / 2 ) / dr_pe5 ) ) + sk_ref"
equation "d8867 = dr_felt_hole"
equation "d8868 = ( dr_pl6x + ( dr_pl0x - dr_pl6x ) * ( ( dr_sc_clear + 0 * ( dr_pe6 - dr_sc_clear - dr_sc_col ) / 4 ) / dr_pe6 ) ) + sk_ref"
equation "d8869 = ( dr_pl6z + ( dr_pl0z - dr_pl6z ) * ( ( dr_sc_clear + 0 * ( dr_pe6 - dr_sc_clear - dr_sc_col ) / 4 ) / dr_pe6 ) ) + sk_ref"
equation "d8870 = dr_felt_hole"
equation "d8871 = ( dr_pl6x + ( dr_pl0x - dr_pl6x ) * ( ( dr_sc_clear + 1 * ( dr_pe6 - dr_sc_clear - dr_sc_col ) / 4 ) / dr_pe6 ) ) + sk_ref"
equation "d8872 = ( dr_pl6z + ( dr_pl0z - dr_pl6z ) * ( ( dr_sc_clear + 1 * ( dr_pe6 - dr_sc_clear - dr_sc_col ) / 4 ) / dr_pe6 ) ) + sk_ref"
equation "d8873 = dr_felt_hole"
equation "d8874 = ( dr_pl6x + ( dr_pl0x - dr_pl6x ) * ( ( dr_sc_clear + 2 * ( dr_pe6 - dr_sc_clear - dr_sc_col ) / 4 ) / dr_pe6 ) ) + sk_ref"
equation "d8875 = ( dr_pl6z + ( dr_pl0z - dr_pl6z ) * ( ( dr_sc_clear + 2 * ( dr_pe6 - dr_sc_clear - dr_sc_col ) / 4 ) / dr_pe6 ) ) + sk_ref"
equation "d8876 = dr_felt_hole"
equation "d8877 = ( dr_pl6x + ( dr_pl0x - dr_pl6x ) * ( ( dr_sc_clear + 3 * ( dr_pe6 - dr_sc_clear - dr_sc_col ) / 4 ) / dr_pe6 ) ) + sk_ref"
equation "d8878 = ( dr_pl6z + ( dr_pl0z - dr_pl6z ) * ( ( dr_sc_clear + 3 * ( dr_pe6 - dr_sc_clear - dr_sc_col ) / 4 ) / dr_pe6 ) ) + sk_ref"
equation "d8879 = dr_felt_hole"
equation "d8880 = ( dr_pl6x + ( dr_pl0x - dr_pl6x ) * ( ( dr_sc_clear + 4 * ( dr_pe6 - dr_sc_clear - dr_sc_col ) / 4 ) / dr_pe6 ) ) + sk_ref"
equation "d8881 = ( dr_pl6z + ( dr_pl0z - dr_pl6z ) * ( ( dr_sc_clear + 4 * ( dr_pe6 - dr_sc_clear - dr_sc_col ) / 4 ) / dr_pe6 ) ) + sk_ref"
equation "d8882 = dr_felt_hole"
equation "d8883 = ( dr_acc_face_y - 1 mm ) * ( 1 )"
equation "d8884 = ( dr_acc_face_y + felt_t + 1 mm ) - ( dr_acc_face_y - 1 mm )"
equation "d8886 = sk_ref"
equation "d8887 = sk_ref"
equation "d8888 = ( ( ( ( fg_rc + dr_fo + fr_w / 2 + -dr_seal_w / 2 ) - ( ( ( fg_vis_zb + fr_wbot / 2 + -dr_seal_w / 2 ) ) * fg_rnz ) ) / fg_rnx ) ) + sk_ref"
equation "d8889 = ( ( -( ( -ab_x + -dr_seal_w / 2 ) ) ) ) + sk_ref"
equation "d8890 = ( ( -( -( ( -pod_w / 2 + dt_xr + fr_w / 2 + -dr_seal_w / 2 ) ) ) ) ) + sk_ref"
equation "d8891 = ( ( ( ( ( -( fg_vis_zt - fr_w / 2 ) + -dr_seal_w / 2 ) ) * fg_dnz - ( -( ( fg_dc + dr_fo + fr_w / 2 + -dr_seal_w / 2 ) ) ) ) / ( -( -fg_dnx ) ) ) ) + sk_ref"
equation "d8892 = ( ( ( ( ( fg_dc + dr_fo + fr_w / 2 + -dr_seal_w / 2 ) ) * fg_rnz - ( ( ( fg_rc + dr_fo + fr_w / 2 + -dr_seal_w / 2 ) ) * fg_dnz ) ) / ( fg_dnx * fg_rnz - ( fg_rnx * fg_dnz ) ) ) ) + sk_ref"
equation "d8893 = ( ( ( fg_rnx * ( ( fg_vis_zb + fr_wbot / 2 + -dr_seal_w / 2 ) ) ) / fg_rnx ) ) + sk_ref"
equation "d8894 = ( ( -( ( -ab_zt + -dr_seal_w / 2 ) ) ) ) + sk_ref"
equation "d8895 = ( ( -( ( -( fg_vis_zt - fr_w / 2 ) + -dr_seal_w / 2 ) ) ) ) + sk_ref"
equation "d8896 = ( ( ( fg_dnx * ( ( fg_rc + dr_fo + fr_w / 2 + -dr_seal_w / 2 ) ) - ( fg_rnx * ( ( fg_dc + dr_fo + fr_w / 2 + -dr_seal_w / 2 ) ) ) ) / ( fg_dnx * fg_rnz - ( fg_rnx * fg_dnz ) ) ) ) + sk_ref"
equation "d8897 = ( -pod_d / 2 + decor_d - dr_back_t ) * ( 1 )"
equation "d8898 = ( dr_acc_face_y - dr_acc_t ) - ( -pod_d / 2 + decor_d - dr_back_t )"
equation "d8900 = sk_ref"
equation "d8901 = sk_ref"
equation "d8902 = ( ( ( ( fg_rc + dr_fo + fr_w / 2 + dr_seal_w / 2 ) - ( ( ( fg_vis_zb + fr_wbot / 2 + dr_seal_w / 2 ) ) * fg_rnz ) ) / fg_rnx ) ) + sk_ref"
equation "d8903 = ( ( -( ( -ab_x + dr_seal_w / 2 ) ) ) ) + sk_ref"
equation "d8904 = ( ( -( -( ( -pod_w / 2 + dt_xr + fr_w / 2 + dr_seal_w / 2 ) ) ) ) ) + sk_ref"
equation "d8905 = ( ( ( ( ( -( fg_vis_zt - fr_w / 2 ) + dr_seal_w / 2 ) ) * fg_dnz - ( -( ( fg_dc + dr_fo + fr_w / 2 + dr_seal_w / 2 ) ) ) ) / ( -( -fg_dnx ) ) ) ) + sk_ref"
equation "d8906 = ( ( ( ( ( fg_dc + dr_fo + fr_w / 2 + dr_seal_w / 2 ) ) * fg_rnz - ( ( ( fg_rc + dr_fo + fr_w / 2 + dr_seal_w / 2 ) ) * fg_dnz ) ) / ( fg_dnx * fg_rnz - ( fg_rnx * fg_dnz ) ) ) ) + sk_ref"
equation "d8907 = ( ( ( fg_rnx * ( ( fg_vis_zb + fr_wbot / 2 + dr_seal_w / 2 ) ) ) / fg_rnx ) ) + sk_ref"
equation "d8908 = ( ( -( ( -ab_zt + dr_seal_w / 2 ) ) ) ) + sk_ref"
equation "d8909 = ( ( -( ( -( fg_vis_zt - fr_w / 2 ) + dr_seal_w / 2 ) ) ) ) + sk_ref"
equation "d8910 = ( ( ( fg_dnx * ( ( fg_rc + dr_fo + fr_w / 2 + dr_seal_w / 2 ) ) - ( fg_rnx * ( ( fg_dc + dr_fo + fr_w / 2 + dr_seal_w / 2 ) ) ) ) / ( fg_dnx * fg_rnz - ( fg_rnx * fg_dnz ) ) ) ) + sk_ref"
equation "d8911 = ( -pod_d / 2 + decor_d - dr_back_t - 1 mm ) * ( 1 )"
equation "d8912 = ( dr_acc_face_y - dr_acc_t + 1 mm ) - ( -pod_d / 2 + decor_d - dr_back_t - 1 mm )"
equation "d8914 = sk_ref"
equation "d8915 = sk_ref"
equation "d8916 = ( ri_x0 + ri_w ) + sk_ref"
equation "d8917 = ( ri_x0 ) + sk_ref"
equation "d8918 = ( ri_y0 ) + sk_ref"
equation "d8919 = ( ri_y0 + ri_d ) + sk_ref"
equation "d8920 = ( fg_vis_zb + dr_skin_t + ri_gap ) * ( 1 )"
equation "d8921 = ( ri_zt ) - ( fg_vis_zb + dr_skin_t + ri_gap )"
equation "d8923 = sk_ref"
equation "d8924 = sk_ref"
equation "d8925 = ( ri_x0 + ri_w - ri_t ) + sk_ref"
equation "d8926 = ( ri_x0 + ri_t ) + sk_ref"
equation "d8927 = ( ri_y0 + ri_t ) + sk_ref"
equation "d8928 = ( ri_y0 + ri_d - ri_t ) + sk_ref"
equation "d8929 = ( fg_vis_zb + dr_skin_t + ri_gap - 1 mm ) * ( 1 )"
equation "d8930 = ( ri_zt + 1 mm ) - ( fg_vis_zb + dr_skin_t + ri_gap - 1 mm )"
equation "d8932 = sk_ref"
equation "d8933 = sk_ref"
equation "d8934 = ( ri_x0 ) + sk_ref"
equation "d8935 = ( ri_x0 + ri_w ) + sk_ref"
equation "d8936 = ( fb_x0 + fb_w ) + sk_ref"
equation "d8937 = ( fb_x0 ) + sk_ref"
equation "d8938 = ( ri_zt ) + sk_ref"
equation "d8939 = ( fb_z0 ) + sk_ref"
equation "d8940 = ( ri_y0 ) * ( 1 )"
equation "d8941 = ( ri_y0 + ri_d ) - ( ri_y0 )"
equation "d8943 = sk_ref"
equation "d8944 = sk_ref"
equation "d8945 = ( fb_x0 + fb_w ) + sk_ref"
equation "d8946 = ( fb_x0 ) + sk_ref"
equation "d8947 = ( fb_y0 ) + sk_ref"
equation "d8948 = ( fb_y0 + fb_d ) + sk_ref"
equation "d8949 = ( fb_z0 ) * ( 1 )"
equation "d8950 = ( fb_z0 + fb_h ) - ( fb_z0 )"
equation "d8952 = sk_ref"
equation "d8953 = sk_ref"
equation "d8954 = ( fb_x0 + fb_w - fb_t ) + sk_ref"
equation "d8955 = ( fb_x0 + fb_t ) + sk_ref"
equation "d8956 = ( fb_y0 + fb_t ) + sk_ref"
equation "d8957 = ( fb_y0 + fb_d - fb_t ) + sk_ref"
equation "d8958 = ( fb_z0 - 1 mm ) * ( 1 )"
equation "d8959 = ( fb_z0 + fb_h + 1 mm ) - ( fb_z0 - 1 mm )"
equation "d8961 = sk_ref"
equation "d8962 = sk_ref"
equation "d8963 = ( fb_x0 + fb_w ) + sk_ref"
equation "d8964 = ( op_x0 + op_w ) + sk_ref"
equation "d8965 = ( fb_x0 ) + sk_ref"
equation "d8966 = ( fb_y0 ) + sk_ref"
equation "d8967 = ( fb_y0 + fb_d - 2 * fb_t ) + sk_ref"
equation "d8968 = ( -pod_d / 2 + decor_d - dr_back_t ) + sk_ref"
equation "d8969 = ( fb_z0 + fb_h ) * ( 1 )"
equation "d8970 = ( op_z0 + op_h ) - ( fb_z0 + fb_h )"
equation "d8972 = sk_ref"
equation "d8973 = sk_ref"
equation "d8974 = ( op_x0 + op_w ) + sk_ref"
equation "d8975 = ( fb_x0 + fb_w ) + sk_ref"